350003_P01_FRONT-DECOR-BLOCK-ASSY-DR_CAD (Autodesk Fusion 360 design; units mm, degrees)
part number: 350003
description: FRONT - AIR SUPPLY ASSY - DR - RESERVED AIR SPACE | Cụm cấp gió khối phải | P01
part number: 350004
description: FRONT - DECOR SKIN - DR | Tấm ốp alu khối phải | P01
part number: 351301
description: FRONT - DECOR BACK PLATE - DR | Tấm hậu khối phải | P01
part number: 351302
description: FRONT - DECOR INNER FACE PANEL - DR - REMOVABLE | Tấm mặt trong tháo được khối phải | P01
part number: 351305
description: FRONT - DECOR INNER PANEL FELT - DR | Nỉ tấm trong khối phải | P01
part number: 351304
description: SEALS - ACCESS PANEL SEAL - 4.0 THICK - VERY SOFT FOAM PSA | Gioăng tấm thăm - xốp rất mềm dày 4.0, keo dán sẵn | P01
part number: 848013
description: FRONT - AIR INTAKE RISER - DR - RESERVED AIR SPACE | Ống gió đứng khối phải | P01
part number: 351402
description: FRONT - AIR TRANSITION - LOWER - DR - RESERVED AIR SPACE | Ống chuyển hướng dưới | P01
part number: 351403
description: FRONT - SUPPLY FAN BOX - DR - RESERVED AIR SPACE | Hộp quạt cấp | P01
part number: 351404
description: FRONT - AIR TRANSITION - UPPER - DR - RESERVED AIR SPACE | Ống chuyển hướng trên | P01
part number: 351405
description: FRONT - DECOR FRAME - DR | Khung trang trí phải (hàn) | P01
part number: 351306
description: FRONT - DECOR FRAME DR - FRONT RING BOTTOM | Mặt trước - khung khối phải - vòng trước - thanh dưới | P01
part number: 352301
description: FRONT - DECOR FRAME DR - FRONT RING FACET SIDE | Mặt trước - khung khối phải - vòng trước - thanh cạnh vát | P01
part number: 352302
description: FRONT - DECOR FRAME DR - FRONT RING TOP | Mặt trước - khung khối phải - vòng trước - thanh trên | P01
part number: 352303
description: FRONT - DECOR FRAME DR - FRONT RING DT JOINT | Mặt trước - khung khối phải - vòng trước - thanh nối khối trên | P01
part number: 352304
description: FRONT - DECOR FRAME DR - FRONT RING DIAGONAL | Mặt trước - khung khối phải - vòng trước - thanh chéo | P01
part number: 352305
description: FRONT - DECOR FRAME DR - FRONT RING GLASS EDGE | Mặt trước - khung khối phải - vòng trước - thanh mép kính | P01
part number: 352306
description: FRONT - DECOR FRAME DR - BACK RING BOTTOM | Mặt trước - khung khối phải - vòng sau - thanh dưới | P01
part number: 352307
description: FRONT - DECOR FRAME DR - BACK RING BOLT LINE | Mặt trước - khung khối phải - vòng sau - thanh hàng bu lông | P01
part number: 352308
description: FRONT - DECOR FRAME DR - BACK RING TOP | Mặt trước - khung khối phải - vòng sau - thanh trên | P01
part number: 352309
description: FRONT - DECOR FRAME DR - BACK RING DT JOINT | Mặt trước - khung khối phải - vòng sau - thanh nối khối trên | P01
part number: 352310
description: FRONT - DECOR FRAME DR - BACK RING DT LEDGE | Mặt trước - khung khối phải - vòng sau - thanh gờ đỡ khối trên | P01
part number: 352311
description: FRONT - DECOR FRAME DR - BACK RING DIAGONAL | Mặt trước - khung khối phải - vòng sau - thanh chéo | P01
part number: 352312
description: FRONT - DECOR FRAME DR - BACK RING GLASS EDGE | Mặt trước - khung khối phải - vòng sau - thanh mép kính | P01
part number: 352313
description: FRONT - DECOR FRAME DR - FRONT RING CROSS 724 | Mặt trước - khung khối phải - vòng trước - thanh ngang 724 | P01
part number: 352314
description: FRONT - DECOR FRAME DR - FRONT RING FAN BOX SHELF | Mặt trước - khung khối phải - vòng trước - thanh đỡ hộp quạt | P01
part number: 352315
description: FRONT - DECOR FRAME DR - FRONT RING CROSS OVER THE FAN BOX | Mặt trước - khung khối phải - vòng trước - thanh ngang trên hộp quạt | P01
part number: 352322
description: FRONT - DECOR FRAME DR - BACK RING BAND | Mặt trước - khung khối phải - vòng sau - thanh đai | P01
part number: 352316
description: FRONT - DECOR FRAME DR - FACET TUBE - 3 OFF | Mặt trước - khung khối phải - thanh mặt vát (3 thanh) | P01
part number: 352317
description: FRONT - DECOR FRAME DR - FACET TUBE FAN BOX SHELF | Mặt trước - khung khối phải - thanh mặt vát - đỡ hộp quạt | P01
part number: 352318
description: FRONT - DECOR FRAME DR - CHAMFER TUBE - 2 OFF | Mặt trước - khung khối phải - thanh vát (2 thanh) | P01
part number: 352319
description: FRONT - DECOR FRAME DR - DT JOINT TUBE SLANTED | Mặt trước - khung khối phải - thanh nối khối trên - xiên | P01
part number: 352320
Autodesk Fusion 360 part; units mm, degrees
(part 1 of 4)
sketch "FRONT - DR OUTLINE (BAND TOP TO ROOF, INNER EDGE ON THE GLASS LINES)" plane through (0, 0, 0) normal (0, 1, 0) x (1, 0, 0) in component "351301 FRONT - DECOR SKIN - DR"
  line L0 (946.8781, -110) -> (1250, -110)
  line L1 (1250, -110) -> (1250, -2400)
  line L2 (1250, -2400) -> (230, -2400)
  line L3 (230, -2400) -> (230, -2120)
  line L4 (230, -2120) -> (749, -1521)
  line L5 (749, -1521) -> (946.8781, -110)
  point P0 (-5000, 5000)
  dimension "d8636" = 5000
  dimension "d8637" = 5000
  dimension "d8638" = 5946.8781
  dimension "d8639" = 6250
  dimension "d8640" = 5230
  dimension "d8641" = 5749
  dimension "d8642" = 5110
  dimension "d8644" = 7120
  dimension "d8645" = 6521
  constraint vertical L1
  constraint vertical L3
  constraint horizontal L0
  constraint horizontal L2
  measures "d8636" horizontal distance of origin P0
  measures "d8637" vertical distance of origin P0
  measures "d8638" horizontal distance of L0.start P0
  measures "d8639" horizontal distance of L0.end P0
  measures "d8640" horizontal distance of L2.end P0
  measures "d8641" horizontal distance of L4.end P0
  measures "d8642" vertical distance of L0.start P0
  measures "d8644" vertical distance of L3.end P0
  measures "d8645" vertical distance of L4.end P0
extrude "EXTRUDE - DR OUTER SHAPE" add sketch "FRONT - DR OUTLINE (BAND TOP TO ROOF, INNER EDGE ON THE GLASS LINES)" along normal blind 205 from surface at -850 makes body 1 in component "351301 FRONT - DECOR SKIN - DR"
sketch "CORNER FACET - DR" plane through (0, 0, 0) normal (0, 0, 1) x (1, 0, 0) in component "351301 FRONT - DECOR SKIN - DR"
  line L0 (1052, -850) -> (1250, -672)
  line L1 (1250, -672) -> (1250, -850)
  line L2 (1250, -850) -> (1052, -850)
  point P0 (-5000, -5000)
  dimension "d8649" = 5000
  dimension "d8650" = 5000
  dimension "d8651" = 6052
  dimension "d8652" = 6250
  dimension "d8654" = 4150
  constraint vertical L1
  constraint horizontal L2
  measures "d8649" horizontal distance of origin P0
  measures "d8650" vertical distance of origin P0
  measures "d8651" horizontal distance of L0.start P0
  measures "d8652" horizontal distance of L0.end P0
  measures "d8654" vertical distance of L1.end P0
extrude "CUT - DR CORNER FACET" cut sketch "CORNER FACET - DR" along normal blind 2400 bodies 1 in component "351301 FRONT - DECOR SKIN - DR"
sketch "JOINT - DR TO DT (v1 LINE TO X 449)" plane through (0, 0, 0) normal (0, 0, 1) x (1, 0, 0) in component "351301 FRONT - DECOR SKIN - DR"
  line L0 (230, -850) -> (449, -672)
  line L1 (449, -672) -> (449, -645)
  line L2 (449, -645) -> (230, -645)
  line L3 (230, -645) -> (230, -850)
  point P0 (-5000, -5000)
  dimension "d8658" = 5000
  dimension "d8659" = 5000
  dimension "d8660" = 5449
  dimension "d8661" = 5230
  dimension "d8662" = 4150
  dimension "d8664" = 4355
  constraint vertical L1
  constraint vertical L3
  constraint horizontal L2
  measures "d8658" horizontal distance of origin P0
  measures "d8659" vertical distance of origin P0
  measures "d8660" horizontal distance of L0.end P0
  measures "d8661" horizontal distance of L2.end P0
  measures "d8662" vertical distance of L0.start P0
  measures "d8664" vertical distance of L1.end P0
extrude "CUT - DR TO DT JOINT" cut sketch "JOINT - DR TO DT (v1 LINE TO X 449)" along normal blind 280 from surface at 2120 bodies 1 in component "351301 FRONT - DECOR SKIN - DR"
sketch "CHAMFER - DR TOP FRONT" plane through (0, 0, 0) normal (1, 0, 0) x (0, 0, -1) in component "351301 FRONT - DECOR SKIN - DR"
  line L0 (-2200, -850) -> (-2400, -672)
  line L1 (-2400, -672) -> (-2400, -850)
  line L2 (-2400, -850) -> (-2200, -850)
  point P0 (5000, -5000)
  dimension "d8668" = 5000
  dimension "d8669" = 5000
  dimension "d8673" = 4150
  constraint vertical L1
  constraint horizontal L2
  measures "d8668" horizontal distance of origin P0
  measures "d8669" vertical distance of origin P0
  measures "d8673" vertical distance of L1.end P0
extrude "CUT - DR TOP CHAMFER" cut sketch "CHAMFER - DR TOP FRONT" along normal blind 2500 from surface at -1250 bodies 1 in component "351301 FRONT - DECOR SKIN - DR"
shell "SHELL - DR SKIN 3 MM (OPEN AT THE BACK AND AT DT)" thickness 3 removed faces 4 at (449, -663, 2213.3333) at (303, -722.3333, 2120) at (1083, -645, 1343.6667) at (376, -731.3333, 2240) on bodies 1 in component "351301 FRONT - DECOR SKIN - DR"
sketch "SLOT - GLASS CHANNEL ALONG THE INNER EDGE" plane through (0, 0, 0) normal (0, 1, 0) x (1, 0, 0) in component "351301 FRONT - DECOR SKIN - DR"
  line L0 (946.8781, -110) -> (962.0249, -110)
  line L1 (962.0249, -110) -> (763.2391, -1527.4726)
  line L2 (763.2391, -1527.4726) -> (249.8472, -2120)
  line L3 (249.8472, -2120) -> (230, -2120)
  line L4 (230, -2120) -> (749, -1521)
  line L5 (749, -1521) -> (946.8781, -110)
  point P0 (-5000, 5000)
  dimension "d8678" = 5000
  dimension "d8679" = 5000
  dimension "d8680" = 5946.8781
  dimension "d8682" = 5763.2391
  dimension "d8684" = 5230
  dimension "d8685" = 5749
  dimension "d8687" = 6527.4726
  dimension "d8689" = 6521
  constraint horizontal L0
  constraint horizontal L3
  measures "d8678" horizontal distance of origin P0
  measures "d8679" vertical distance of origin P0
  measures "d8680" horizontal distance of L0.start P0
  measures "d8682" horizontal distance of L1.end P0
  measures "d8684" horizontal distance of L3.end P0
  measures "d8685" horizontal distance of L4.end P0
  measures "d8687" vertical distance of L1.end P0
  measures "d8689" vertical distance of L4.end P0
extrude "CUT - SKIN SLOT FOR THE GLASS CHANNEL" cut sketch "SLOT - GLASS CHANNEL ALONG THE INNER EDGE" along normal blind 17 from surface at -707.5 bodies 1 in component "351301 FRONT - DECOR SKIN - DR"
sketch "INTAKE - DR BASE OPEN OVER THE MESH BAND PIECE" plane through (0, 0, 0) normal (0, 0, 1) x (1, 0, 0) in component "351301 FRONT - DECOR SKIN - DR"
  line L0 (949.4867, -847) -> (1050.8498, -847)
  line L1 (1050.8498, -847) -> (1247, -670.6629)
  line L2 (1247, -670.6629) -> (1247, -646.5)
  line L3 (1247, -646.5) -> (949.4867, -646.5)
  line L4 (949.4867, -646.5) -> (949.4867, -847)
  point P0 (-5000, -5000)
  dimension "d8693" = 5000
  dimension "d8694" = 5000
  dimension "d8695" = 6050.8498
  dimension "d8696" = 6247
  dimension "d8697" = 5949.4867
  dimension "d8698" = 4153
  dimension "d8699" = 4329.3371
  dimension "d8700" = 4353.5
  constraint vertical L2
  constraint vertical L4
  constraint horizontal L0
  constraint horizontal L3
  measures "d8693" horizontal distance of origin P0
  measures "d8694" vertical distance of origin P0
  measures "d8695" horizontal distance of L0.end P0
  measures "d8696" horizontal distance of L1.end P0
  measures "d8697" horizontal distance of L3.end P0
  measures "d8698" vertical distance of L0.start P0
  measures "d8699" vertical distance of L1.end P0
  measures "d8700" vertical distance of L2.end P0
extrude "CUT - BASE OPENING OVER THE BAND PIECE" cut sketch "INTAKE - DR BASE OPEN OVER THE MESH BAND PIECE" along normal blind 5 from surface at 109 bodies 1 in component "351301 FRONT - DECOR SKIN - DR"
sketch "OUTLINE - DR BACK PLATE (FIXED STRIP AND TOP BAND)" plane through (0, 0, 0) normal (0, 1, 0) x (1, 0, 0) in component "351302 FRONT - DECOR BACK PLATE - DR"
  line L0 (1203.5, -113) -> (1247, -113)
  line L1 (1247, -113) -> (1247, -2397)
  line L2 (1247, -2397) -> (449, -2397)
  line L3 (449, -2397) -> (449, -2155)
  line L4 (449, -2155) -> (1203.5, -2155)
  line L5 (1203.5, -2155) -> (1203.5, -113)
  point P0 (-5000, 5000)
  dimension "d8704" = 5000
  dimension "d8705" = 5000
  dimension "d8706" = 6247
  dimension "d8707" = 5449
  dimension "d8708" = 6203.5
  constraint vertical L1
  constraint vertical L3
  constraint vertical L5
  constraint horizontal L0
  constraint horizontal L2
  constraint horizontal L4
  measures "d8704" horizontal distance of origin P0
  measures "d8705" vertical distance of origin P0
  measures "d8706" horizontal distance of L0.end P0
  measures "d8707" horizontal distance of L2.end P0
  measures "d8708" horizontal distance of L4.end P0
extrude "EXTRUDE - DR BACK PLATE" add sketch "OUTLINE - DR BACK PLATE (FIXED STRIP AND TOP BAND)" along normal blind 1.5 from surface at -646.5 separate body makes body 2 in component "351302 FRONT - DECOR BACK PLATE - DR"
sketch "HOLES - J-FRONT-01 RIVNUTS (6)" plane through (0, 0, 0) normal (0, 1, 0) x (1, 0, 0) in component "351302 FRONT - DECOR BACK PLATE - DR"
  circle A0 centre (1224, -332.26) radius 5
  circle A1 centre (1224, -683.63) radius 5
  circle A2 centre (1224, -1035) radius 5
  circle A3 centre (1224, -1477.26) radius 5
  circle A4 centre (1224, -1828.63) radius 5
  circle A5 centre (1224, -2180) radius 5
  point P0 (-5000, 5000)
  dimension "d8715" = 5000
  dimension "d8716" = 5000
  dimension "d8718" = 5332.26
  dimension "d8719" = 10
  dimension "d8721" = 5683.63
  dimension "d8722" = 10
  dimension "d8724" = 6035
  dimension "d8725" = 10
  dimension "d8727" = 6477.26
  dimension "d8728" = 10
  dimension "d8730" = 6828.63
  dimension "d8731" = 10
  dimension "d8733" = 7180
  dimension "d8734" = 10
  measures "d8715" horizontal distance of origin P0
  measures "d8716" vertical distance of origin P0
  measures "d8718" vertical distance of P0 A0.centre
  measures "d8719" diameter of A0
  measures "d8721" vertical distance of P0 A1.centre
  measures "d8722" diameter of A1
  measures "d8724" vertical distance of P0 A2.centre
  measures "d8725" diameter of A2
  measures "d8727" vertical distance of P0 A3.centre
  measures "d8728" diameter of A3
  measures "d8730" vertical distance of P0 A4.centre
  measures "d8731" diameter of A4
  measures "d8733" vertical distance of P0 A5.centre
  measures "d8734" diameter of A5
extrude "CUT - J-FRONT-01 RIVNUT HOLES" cut sketch "HOLES - J-FRONT-01 RIVNUTS (6)" along normal blind 3.5 from surface at -647.5 bodies 2 in component "351302 FRONT - DECOR BACK PLATE - DR"
sketch "OUTLINE - DR INNER FACE PANEL (REMOVABLE, D-87, D-130)" plane through (0, 0, 0) normal (0, 1, 0) x (1, 0, 0) in component "351305 FRONT - DECOR INNER FACE PANEL - DR - REMOVABLE"
  line L0 (949.4867, -113) -> (1203.5, -113)
  line L1 (1203.5, -113) -> (1203.5, -2155)
  line L2 (1203.5, -2155) -> (449, -2155)
  line L3 (449, -2155) -> (449, -2120)
  line L4 (449, -2120) -> (233.9694, -2120)
  line L5 (233.9694, -2120) -> (751.8478, -1522.2945)
  line L6 (751.8478, -1522.2945) -> (949.4867, -113)
  point P0 (-5000, 5000)
  dimension "d8738" = 5000
  dimension "d8739" = 5000
  dimension "d8740" = 5949.4867
  dimension "d8741" = 6203.5
  dimension "d8742" = 5449
  dimension "d8744" = 5751.8478
  dimension "d8748" = 6522.2945
  constraint vertical L1
  constraint vertical L3
  constraint horizontal L0
  constraint horizontal L2
  constraint horizontal L4
  measures "d8738" horizontal distance of origin P0
  measures "d8739" vertical distance of origin P0
  measures "d8740" horizontal distance of L0.start P0
  measures "d8741" horizontal distance of L0.end P0
  measures "d8742" horizontal distance of L2.end P0
  measures "d8744" horizontal distance of L5.end P0
  measures "d8748" vertical distance of L5.end P0
extrude "EXTRUDE - DR INNER FACE PANEL" add sketch "OUTLINE - DR INNER FACE PANEL (REMOVABLE, D-87, D-130)" along normal blind 3 from surface at -644.14 separate body makes body 3 in component "351305 FRONT - DECOR INNER FACE PANEL - DR - REMOVABLE"
sketch "OPENING - INTO THE AIR COLUMN TOP" plane through (0, 0, 0) normal (0, 1, 0) x (1, 0, 0) in component "351305 FRONT - DECOR INNER FACE PANEL - DR - REMOVABLE"
  line L0 (961, -1895) -> (1146, -1895)
  line L1 (1146, -1895) -> (1146, -2102)
  line L2 (1146, -2102) -> (961, -2102)
  line L3 (961, -2102) -> (961, -1895)
  point P0 (-5000, 5000)
  dimension "d8752" = 5000
  dimension "d8753" = 5000
  dimension "d8754" = 6146
  dimension "d8755" = 5961
  dimension "d8756" = 6895
  dimension "d8757" = 7102
  constraint vertical L1
  constraint vertical L3
  constraint horizontal L0
  constraint horizontal L2
  measures "d8752" horizontal distance of origin P0
  measures "d8753" vertical distance of origin P0
  measures "d8754" horizontal distance of L0.end P0
  measures "d8755" horizontal distance of L2.end P0
  measures "d8756" vertical distance of L0.start P0
  measures "d8757" vertical distance of L1.end P0
extrude "CUT - OPENING INTO THE AIR COLUMN" cut sketch "OPENING - INTO THE AIR COLUMN TOP" along normal blind 5 from surface at -645.14 bodies 3 in component "351305 FRONT - DECOR INNER FACE PANEL - DR - REMOVABLE"
sketch "HOLES - THE PANEL'S SCREWS (21)" plane through (0, 0, 0) normal (0, 1, 0) x (1, 0, 0) in component "351305 FRONT - DECOR INNER FACE PANEL - DR - REMOVABLE"
  circle A0 centre (1000.2299, -130) radius 3.5
  circle A1 centre (1146, -130) radius 3.5
  circle A2 centre (1186, -170) radius 3.5
  circle A3 centre (1186, -556.2) radius 3.5
  circle A4 centre (1186, -942.4) radius 3.5
  circle A5 centre (1186, -1328.6) radius 3.5
  circle A6 centre (1186, -1714.8) radius 3.5
  circle A7 centre (1186, -2101) radius 3.5
  circle A8 centre (1143.5, -2141) radius 3.5
  circle A9 centre (821.25, -2141) radius 3.5
  circle A10 centre (499, -2141) radius 3.5
  circle A11 centre (419, -2110) radius 3.5
  circle A12 centre (299.8348, -2110) radius 3.5
  circle A13 centre (286.0282, -2079.7691) radius 3.5
  circle A14 centre (512.0116, -1818.9521) radius 3.5
  circle A15 centre (737.995, -1558.135) radius 3.5
  circle A16 centre (769.7436, -1488.2918) radius 3.5
  circle A17 centre (812.0577, -1186.5645) radius 3.5
  circle A18 centre (854.3718, -884.8373) radius 3.5
  circle A19 centre (896.6859, -583.11) radius 3.5
  circle A20 centre (939, -281.3828) radius 3.5
  point P0 (-5000, 5000)
  dimension "d8761" = 5000
  dimension "d8762" = 5000
  dimension "d8763" = 6000.2299
  dimension "d8764" = 5130
  dimension "d8765" = 7
  dimension "d8766" = 6146
  dimension "d8767" = 5130
  dimension "d8768" = 7
  dimension "d8769" = 6186
  dimension "d8770" = 5170
  dimension "d8771" = 7
  dimension "d8772" = 6186
  dimension "d8773" = 5556.2
  dimension "d8774" = 7
  dimension "d8775" = 6186
  dimension "d8776" = 5942.4
  dimension "d8777" = 7
  dimension "d8778" = 6186
  dimension "d8779" = 6328.6
  dimension "d8780" = 7
  dimension "d8781" = 6186
  dimension "d8782" = 6714.8
  dimension "d8783" = 7
  dimension "d8784" = 6186
  dimension "d8785" = 7101
  dimension "d8786" = 7
  dimension "d8787" = 6143.5
  dimension "d8788" = 7141
  dimension "d8789" = 7
  dimension "d8790" = 5821.25
  dimension "d8791" = 7141
  dimension "d8792" = 7
  dimension "d8793" = 5499
  dimension "d8794" = 7141
  dimension "d8795" = 7
  dimension "d8796" = 5419
  dimension "d8797" = 7110
  dimension "d8798" = 7
  dimension "d8799" = 5299.8348
  dimension "d8800" = 7110
  dimension "d8801" = 7
  dimension "d8802" = 5286.0282
  dimension "d8803" = 7079.7691
  dimension "d8804" = 7
  dimension "d8805" = 5512.0116
  dimension "d8806" = 6818.9521
  dimension "d8807" = 7
  dimension "d8808" = 5737.995
  dimension "d8809" = 6558.135
  dimension "d8810" = 7
  dimension "d8811" = 5769.7436
  dimension "d8812" = 6488.2918
  dimension "d8813" = 7
  dimension "d8814" = 5812.0577
  dimension "d8815" = 6186.5645
  dimension "d8816" = 7
  dimension "d8817" = 5854.3718
  dimension "d8818" = 5884.8373
  dimension "d8819" = 7
  dimension "d8820" = 5896.6859
  dimension "d8821" = 5583.11
  dimension "d8822" = 7
  dimension "d8823" = 5939
  dimension "d8824" = 5281.3828
  dimension "d8825" = 7
  measures "d8761" horizontal distance of origin P0
  measures "d8762" vertical distance of origin P0
  measures "d8763" horizontal distance of P0 A0.centre
  measures "d8764" vertical distance of P0 A0.centre
  measures "d8765" diameter of A0
  measures "d8766" horizontal distance of P0 A1.centre
  measures "d8767" vertical distance of P0 A1.centre
  measures "d8768" diameter of A1
  measures "d8769" horizontal distance of P0 A2.centre
  measures "d8770" vertical distance of P0 A2.centre
  measures "d8771" diameter of A2
  measures "d8772" horizontal distance of P0 A3.centre
  measures "d8773" vertical distance of P0 A3.centre
  measures "d8774" diameter of A3
  measures "d8775" horizontal distance of P0 A4.centre
  measures "d8776" vertical distance of P0 A4.centre
  measures "d8777" diameter of A4
  measures "d8778" horizontal distance of P0 A5.centre
  measures "d8779" vertical distance of P0 A5.centre
  measures "d8780" diameter of A5
  measures "d8781" horizontal distance of P0 A6.centre
  measures "d8782" vertical distance of P0 A6.centre
  measures "d8783" diameter of A6
  measures "d8784" horizontal distance of P0 A7.centre
  measures "d8785" vertical distance of P0 A7.centre
  measures "d8786" diameter of A7
  measures "d8787" horizontal distance of P0 A8.centre
  measures "d8788" vertical distance of P0 A8.centre
  measures "d8789" diameter of A8
  measures "d8790" horizontal distance of P0 A9.centre
  measures "d8791" vertical distance of P0 A9.centre
  measures "d8792" diameter of A9
  measures "d8793" horizontal distance of P0 A10.centre
  measures "d8794" vertical distance of P0 A10.centre
  measures "d8795" diameter of A10
  measures "d8796" horizontal distance of P0 A11.centre
  measures "d8797" vertical distance of P0 A11.centre
  measures "d8798" diameter of A11
  measures "d8799" horizontal distance of P0 A12.centre
  measures "d8800" vertical distance of P0 A12.centre
  measures "d8801" diameter of A12
  measures "d8802" horizontal distance of P0 A13.centre
  measures "d8803" vertical distance of P0 A13.centre
  measures "d8804" diameter of A13
  measures "d8805" horizontal distance of P0 A14.centre
  measures "d8806" vertical distance of P0 A14.centre
  measures "d8807" diameter of A14
  measures "d8808" horizontal distance of P0 A15.centre
  measures "d8809" vertical distance of P0 A15.centre
  measures "d8810" diameter of A15
  measures "d8811" horizontal distance of P0 A16.centre
  measures "d8812" vertical distance of P0 A16.centre
  measures "d8813" diameter of A16
  measures "d8814" horizontal distance of P0 A17.centre
  measures "d8815" vertical distance of P0 A17.centre
  measures "d8816" diameter of A17
  measures "d8817" horizontal distance of P0 A18.centre
  measures "d8818" vertical distance of P0 A18.centre
  measures "d8819" diameter of A18
  measures "d8820" horizontal distance of P0 A19.centre
  measures "d8821" vertical distance of P0 A19.centre
  measures "d8822" diameter of A19
  measures "d8823" horizontal distance of P0 A20.centre
  measures "d8824" vertical distance of P0 A20.centre
  measures "d8825" diameter of A20
extrude "CUT - THE PANEL'S SCREW HOLES" cut sketch "HOLES - THE PANEL'S SCREWS (21)" along normal blind 5 from surface at -645.14 bodies 3 in component "351305 FRONT - DECOR INNER FACE PANEL - DR - REMOVABLE"
sketch "HOLES - AIR COLUMN HOOK STUD RIVNUTS (2)" plane through (0, 0, 0) normal (0, 1, 0) x (1, 0, 0) in component "351305 FRONT - DECOR INNER FACE PANEL - DR - REMOVABLE"
  circle A0 centre (971, -1700) radius 5
  circle A1 centre (971, -1850) radius 5
  point P0 (-5000, 5000)
  dimension "d8829" = 5000
  dimension "d8830" = 5000
  dimension "d8832" = 6700
  dimension "d8833" = 10
  dimension "d8835" = 6850
  dimension "d8836" = 10
  measures "d8829" horizontal distance of origin P0
  measures "d8830" vertical distance of origin P0
  measures "d8832" vertical distance of P0 A0.centre
  measures "d8833" diameter of A0
  measures "d8835" vertical distance of P0 A1.centre
  measures "d8836" diameter of A1
extrude "CUT - HOOK STUD RIVNUT HOLES" cut sketch "HOLES - AIR COLUMN HOOK STUD RIVNUTS (2)" along normal blind 5 from surface at -645.14 bodies 3 in component "351305 FRONT - DECOR INNER FACE PANEL - DR - REMOVABLE"
sketch "OUTLINE - DR INNER FACE PANEL FELT" plane through (0, 0, 0) normal (0, 1, 0) x (1, 0, 0) in component "351304 FRONT - DECOR INNER PANEL FELT - DR"
  line L0 (949, -116.4706) -> (949, -2120)
  line L1 (949, -2120) -> (233.9694, -2120)
  line L2 (233.9694, -2120) -> (751.8478, -1522.2945)
  line L3 (751.8478, -1522.2945) -> (949, -116.4706)
  point P0 (-5000, 5000)
  dimension "d8840" = 5000
  dimension "d8841" = 5000
  dimension "d8842" = 5949
  dimension "d8844" = 5751.8478
  dimension "d8845" = 5116.4706
  dimension "d8847" = 6522.2945
  constraint vertical L0
  constraint horizontal L1
  measures "d8840" horizontal distance of origin P0
  measures "d8841" vertical distance of origin P0
  measures "d8842" horizontal distance of L0.start P0
  measures "d8844" horizontal distance of L2.end P0
  measures "d8845" vertical distance of L0.start P0
  measures "d8847" vertical distance of L2.end P0
extrude "EXTRUDE - FELT 9" add sketch "OUTLINE - DR INNER FACE PANEL FELT" along normal blind 9 from surface at -641.14 separate body makes body 4 in component "351304 FRONT - DECOR INNER PANEL FELT - DR"
sketch "HOLES - OVER THE PANEL'S SCREW HEADS, PLUGGED (10)" plane through (0, 0, 0) normal (0, 1, 0) x (1, 0, 0) in component "351304 FRONT - DECOR INNER PANEL FELT - DR"
  circle A0 centre (419, -2110) radius 7
  circle A1 centre (299.8348, -2110) radius 7
  circle A2 centre (286.0282, -2079.7691) radius 7
  circle A3 centre (512.0116, -1818.9521) radius 7
  circle A4 centre (737.995, -1558.135) radius 7
  circle A5 centre (769.7436, -1488.2918) radius 7
  circle A6 centre (812.0577, -1186.5645) radius 7
  circle A7 centre (854.3718, -884.8373) radius 7
  circle A8 centre (896.6859, -583.11) radius 7
  circle A9 centre (939, -281.3828) radius 7
  point P0 (-5000, 5000)
  dimension "d8851" = 5000
  dimension "d8852" = 5000
  dimension "d8853" = 5419
  dimension "d8854" = 7110
  dimension "d8855" = 14
  dimension "d8856" = 5299.8348
  dimension "d8857" = 7110
  dimension "d8858" = 14
  dimension "d8859" = 5286.0282
  dimension "d8860" = 7079.7691
  dimension "d8861" = 14
  dimension "d8862" = 5512.0116
  dimension "d8863" = 6818.9521
  dimension "d8864" = 14
  dimension "d8865" = 5737.995
  dimension "d8866" = 6558.135
  dimension "d8867" = 14
  dimension "d8868" = 5769.7436
  dimension "d8869" = 6488.2918
  dimension "d8870" = 14
  dimension "d8871" = 5812.0577
  dimension "d8872" = 6186.5645
  dimension "d8873" = 14
  dimension "d8874" = 5854.3718
  dimension "d8875" = 5884.8373
  dimension "d8876" = 14
  dimension "d8877" = 5896.6859
  dimension "d8878" = 5583.11
  dimension "d8879" = 14
  dimension "d8880" = 5939
  dimension "d8881" = 5281.3828
  dimension "d8882" = 14
  measures "d8851" horizontal distance of origin P0
  measures "d8852" vertical distance of origin P0
  measures "d8853" horizontal distance of P0 A0.centre
  measures "d8854" vertical distance of P0 A0.centre
  measures "d8855" diameter of A0
  measures "d8856" horizontal distance of P0 A1.centre
  measures "d8857" vertical distance of P0 A1.centre
  measures "d8858" diameter of A1
  measures "d8859" horizontal distance of P0 A2.centre
  measures "d8860" vertical distance of P0 A2.centre
  measures "d8861" diameter of A2
  measures "d8862" horizontal distance of P0 A3.centre
  measures "d8863" vertical distance of P0 A3.centre
  measures "d8864" diameter of A3
  measures "d8865" horizontal distance of P0 A4.centre
  measures "d8866" vertical distance of P0 A4.centre
  measures "d8867" diameter of A4
  measures "d8868" horizontal distance of P0 A5.centre
  measures "d8869" vertical distance of P0 A5.centre
  measures "d8870" diameter of A5
  measures "d8871" horizontal distance of P0 A6.centre
  measures "d8872" vertical distance of P0 A6.centre
  measures "d8873" diameter of A6
  measures "d8874" horizontal distance of P0 A7.centre
  measures "d8875" vertical distance of P0 A7.centre
  measures "d8876" diameter of A7
  measures "d8877" horizontal distance of P0 A8.centre
  measures "d8878" vertical distance of P0 A8.centre
  measures "d8879" diameter of A8
  measures "d8880" horizontal distance of P0 A9.centre
  measures "d8881" vertical distance of P0 A9.centre
  measures "d8882" diameter of A9
extrude "CUT - FELT HOLES OVER THE SCREW HEADS" cut sketch "HOLES - OVER THE PANEL'S SCREW HEADS, PLUGGED (10)" along normal blind 11 from surface at -642.14 bodies 4 in component "351304 FRONT - DECOR INNER PANEL FELT - DR"
sketch "OUTLINE - 848013 SEAL, OUTER EDGE" plane through (0, 0, 0) normal (0, 1, 0) x (1, 0, 0) in component "848013 SEALS - ACCESS PANEL SEAL - 4.0 THICK - VERY SOFT FOAM PSA"
  line L0 (956.7517, -126) -> (1190, -126)
  line L1 (1190, -126) -> (1190, -2145)
  line L2 (1190, -2145) -> (455, -2145)
  line L3 (455, -2145) -> (455, -2114)
  line L4 (455, -2114) -> (251.0765, -2114)
  line L5 (251.0765, -2114) -> (760.3913, -1526.1781)
  line L6 (760.3913, -1526.1781) -> (956.7517, -126)
  point P0 (-5000, 5000)
  dimension "d8886" = 5000
  dimension "d8887" = 5000
  dimension "d8888" = 5956.7517
  dimension "d8889" = 6190
  dimension "d8890" = 5455
  dimension "d8891" = 5251.0765
  dimension "d8892" = 5760.3913
  dimension "d8893" = 5126
  dimension "d8894" = 7145
  dimension "d8895" = 7114
  dimension "d8896" = 6526.1781
  constraint vertical L1
  constraint vertical L3
  constraint horizontal L0
  constraint horizontal L2
  constraint horizontal L4
  measures "d8886" horizontal distance of origin P0
  measures "d8887" vertical distance of origin P0
  measures "d8888" horizontal distance of L0.start P0
  measures "d8889" horizontal distance of L0.end P0
  measures "d8890" horizontal distance of L2.end P0
  measures "d8891" horizontal distance of L4.end P0
  measures "d8892" horizontal distance of L5.end P0
  measures "d8893" vertical distance of L0.start P0
  measures "d8894" vertical distance of L1.end P0
  measures "d8895" vertical distance of L3.end P0
  measures "d8896" vertical distance of L5.end P0
extrude "EXTRUDE - 848013 SEAL (SQUEEZED TO THE STOP GAP)" add sketch "OUTLINE - 848013 SEAL, OUTER EDGE" along normal blind 2.36 from surface at -646.5 separate body makes body 5 in component "848013 SEALS - ACCESS PANEL SEAL - 4.0 THICK - VERY SOFT FOAM PSA"
sketch "OUTLINE - 848013 SEAL, INNER EDGE" plane through (0, 0, 0) normal (0, 1, 0) x (1, 0, 0) in component "848013 SEALS - ACCESS PANEL SEAL - 4.0 THICK - VERY SOFT FOAM PSA"
  line L0 (963.708, -134) -> (1182, -134)
  line L1 (1182, -134) -> (1182, -2137)
  line L2 (1182, -2137) -> (463, -2137)
  line L3 (463, -2137) -> (463, -2106)
  line L4 (463, -2106) -> (268.5932, -2106)
  line L5 (268.5932, -2106) -> (767.9854, -1529.6302)
  line L6 (767.9854, -1529.6302) -> (963.708, -134)
  point P0 (-5000, 5000)
  dimension "d8900" = 5000
  dimension "d8901" = 5000
  dimension "d8902" = 5963.708
  dimension "d8903" = 6182
  dimension "d8904" = 5463
  dimension "d8905" = 5268.5932
  dimension "d8906" = 5767.9854
  dimension "d8907" = 5134
  dimension "d8908" = 7137
  dimension "d8909" = 7106
  dimension "d8910" = 6529.6302
  constraint vertical L1
  constraint vertical L3
  constraint horizontal L0
  constraint horizontal L2
  constraint horizontal L4
  measures "d8900" horizontal distance of origin P0
  measures "d8901" vertical distance of origin P0
  measures "d8902" horizontal distance of L0.start P0
  measures "d8903" horizontal distance of L0.end P0
  measures "d8904" horizontal distance of L2.end P0
  measures "d8905" horizontal distance of L4.end P0
  measures "d8906" horizontal distance of L5.end P0
  measures "d8907" vertical distance of L0.start P0
  measures "d8908" vertical distance of L1.end P0
  measures "d8909" vertical distance of L3.end P0
  measures "d8910" vertical distance of L5.end P0
extrude "CUT - 848013 SEAL, INSIDE THE LOOP" cut sketch "OUTLINE - 848013 SEAL, INNER EDGE" along normal blind 4.36 from surface at -647.5 bodies 5 in component "848013 SEALS - ACCESS PANEL SEAL - 4.0 THICK - VERY SOFT FOAM PSA"
sketch "PLAN - INTAKE RISER OUTER" plane through (0, 0, 0) normal (0, 0, 1) x (1, 0, 0) in component "351402 FRONT - AIR INTAKE RISER - DR - RESERVED AIR SPACE"
  line L0 (959, -803) -> (1098, -803)
  line L1 (1098, -803) -> (1098, -648)
  line L2 (1098, -648) -> (959, -648)
  line L3 (959, -648) -> (959, -803)
  point P0 (-5000, -5000)
  dimension "d8914" = 5000
  dimension "d8915" = 5000
  dimension "d8916" = 6098
  dimension "d8917" = 5959
  dimension "d8918" = 4197
  dimension "d8919" = 4352
  constraint vertical L1
  constraint vertical L3
  constraint horizontal L0
  constraint horizontal L2
  measures "d8914" horizontal distance of origin P0
  measures "d8915" vertical distance of origin P0
  measures "d8916" horizontal distance of L0.end P0
  measures "d8917" horizontal distance of L2.end P0
  measures "d8918" vertical distance of L0.start P0
  measures "d8919" vertical distance of L1.end P0
extrude "EXTRUDE - INTAKE RISER" add sketch "PLAN - INTAKE RISER OUTER" along normal blind 1192 from surface at 253 separate body makes body 6 in component "351402 FRONT - AIR INTAKE RISER - DR - RESERVED AIR SPACE"
sketch "PLAN - INTAKE RISER BORE" plane through (0, 0, 0) normal (0, 0, 1) x (1, 0, 0) in component "351402 FRONT - AIR INTAKE RISER - DR - RESERVED AIR SPACE"
  line L0 (960, -802) -> (1097, -802)
  line L1 (1097, -802) -> (1097, -649)
  line L2 (1097, -649) -> (960, -649)
  line L3 (960, -649) -> (960, -802)
  point P0 (-5000, -5000)
  dimension "d8923" = 5000
  dimension "d8924" = 5000
  dimension "d8925" = 6097
  dimension "d8926" = 5960
  dimension "d8927" = 4198
  dimension "d8928" = 4351
  constraint vertical L1
  constraint vertical L3
  constraint horizontal L0
  constraint horizontal L2
  measures "d8923" horizontal distance of origin P0
  measures "d8924" vertical distance of origin P0
  measures "d8925" horizontal distance of L0.end P0
  measures "d8926" horizontal distance of L2.end P0
  measures "d8927" vertical distance of L0.start P0
  measures "d8928" vertical distance of L1.end P0
extrude "CUT - INTAKE RISER BORE" cut sketch "PLAN - INTAKE RISER BORE" along normal blind 1194 from surface at 252 bodies 6 in component "351402 FRONT - AIR INTAKE RISER - DR - RESERVED AIR SPACE"
sketch "SIDE - LOWER TRANSITION SPACE" plane through (0, 0, 0) normal (0, 1, 0) x (1, 0, 0) in component "351403 FRONT - AIR TRANSITION - LOWER - DR - RESERVED AIR SPACE"
  line L0 (959, -1445) -> (1098, -1445)
  line L1 (1098, -1445) -> (980, -1650)
  line L2 (980, -1650) -> (680, -1650)
  line L3 (680, -1650) -> (959, -1445)
  point P0 (-5000, 5000)
  dimension "d8932" = 5000
  dimension "d8933" = 5000
  dimension "d8934" = 5959
  dimension "d8935" = 6098
  dimension "d8936" = 5980
  dimension "d8937" = 5680
  dimension "d8939" = 6650
  constraint horizontal L0
  constraint horizontal L2
  measures "d8932" horizontal distance of origin P0
  measures "d8933" vertical distance of origin P0
  measures "d8934" horizontal distance of L0.start P0
  measures "d8935" horizontal distance of L0.end P0
  measures "d8936" horizontal distance of L1.end P0
  measures "d8937" horizontal distance of L2.end P0
  measures "d8939" vertical distance of L1.end P0
extrude "EXTRUDE - LOWER TRANSITION SPACE" add sketch "SIDE - LOWER TRANSITION SPACE" along normal blind 155 from surface at -803 separate body makes body 7 in component "351403 FRONT - AIR TRANSITION - LOWER - DR - RESERVED AIR SPACE"
sketch "PLAN - FAN BOX OUTER" plane through (0, 0, 0) normal (0, 0, 1) x (1, 0, 0) in component "351404 FRONT - SUPPLY FAN BOX - DR - RESERVED AIR SPACE"
  line L0 (680, -819) -> (980, -819)
  line L1 (980, -819) -> (980, -664)
  line L2 (980, -664) -> (680, -664)
  line L3 (680, -664) -> (680, -819)
  point P0 (-5000, -5000)
  dimension "d8943" = 5000
  dimension "d8944" = 5000
  dimension "d8945" = 5980
  dimension "d8946" = 5680
  dimension "d8947" = 4181
  dimension "d8948" = 4336
  constraint vertical L1
  constraint vertical L3
  constraint horizontal L0
  constraint horizontal L2
  measures "d8943" horizontal distance of origin P0
  measures "d8944" vertical distance of origin P0
  measures "d8945" horizontal distance of L0.end P0
  measures "d8946" horizontal distance of L2.end P0
  measures "d8947" vertical distance of L0.start P0
  measures "d8948" vertical distance of L1.end P0
extrude "EXTRUDE - FAN BOX" add sketch "PLAN - FAN BOX OUTER" along normal blind 300 from surface at 1650 separate body makes body 8 in component "351404 FRONT - SUPPLY FAN BOX - DR - RESERVED AIR SPACE"
sketch "PLAN - FAN BOX BORE" plane through (0, 0, 0) normal (0, 0, 1) x (1, 0, 0) in component "351404 FRONT - SUPPLY FAN BOX - DR - RESERVED AIR SPACE"
  line L0 (682, -817) -> (978, -817)
  line L1 (978, -817) -> (978, -666)
  line L2 (978, -666) -> (682, -666)
  line L3 (682, -666) -> (682, -817)
  point P0 (-5000, -5000)
  dimension "d8952" = 5000
  dimension "d8953" = 5000
  dimension "d8954" = 5978
  dimension "d8955" = 5682
  dimension "d8956" = 4183
  dimension "d8957" = 4334
  constraint vertical L1
  constraint vertical L3
  constraint horizontal L0
  constraint horizontal L2
  measures "d8952" horizontal distance of origin P0
  measures "d8953" vertical distance of origin P0
  measures "d8954" horizontal distance of L0.end P0
  measures "d8955" horizontal distance of L2.end P0
  measures "d8956" vertical distance of L0.start P0
  measures "d8957" vertical distance of L1.end P0
extrude "CUT - FAN BOX BORE" cut sketch "PLAN - FAN BOX BORE" along normal blind 302 from surface at 1649 bodies 8 in component "351404 FRONT - SUPPLY FAN BOX - DR - RESERVED AIR SPACE"
sketch "PLAN - UPPER TRANSITION SPACE" plane through (0, 0, 0) normal (0, 0, 1) x (1, 0, 0) in component "351405 FRONT - AIR TRANSITION - UPPER - DR - RESERVED AIR SPACE"
  line L0 (680, -819) -> (980, -819)
  line L1 (980, -819) -> (980, -668)
  line L2 (980, -668) -> (1146, -668)
  line L3 (1146, -668) -> (1146, -646.5)
  line L4 (1146, -646.5) -> (680, -646.5)
  line L5 (680, -646.5) -> (680, -819)
  point P0 (-5000, -5000)
  dimension "d8961" = 5000
  dimension "d8962" = 5000
  dimension "d8963" = 5980
  dimension "d8964" = 6146
  dimension "d8965" = 5680
  dimension "d8966" = 4181
  dimension "d8967" = 4332
  dimension "d8968" = 4353.5
  constraint vertical L1
  constraint vertical L3
  constraint vertical L5
  constraint horizontal L0
  constraint horizontal L2
  constraint horizontal L4
  measures "d8961" horizontal distance of origin P0
  measures "d8962" vertical distance of origin P0
  measures "d8963" horizontal distance of L0.end P0
  measures "d8964" horizontal distance of L2.end P0
  measures "d8965" horizontal distance of L4.end P0
  measures "d8966" vertical distance of L0.start P0
  measures "d8967" vertical distance of L1.end P0
  measures "d8968" vertical distance of L3.end P0
extrude "EXTRUDE - UPPER TRANSITION SPACE" add sketch "PLAN - UPPER TRANSITION SPACE" along normal blind 152 from surface at 1950 separate body makes body 9 in component "351405 FRONT - AIR TRANSITION - UPPER - DR - RESERVED AIR SPACE"
sketch "PLAN - UPPER TRANSITION DROP TO THE OPENING" plane through (0, 0, 0) normal (0, 0, 1) x (1, 0, 0) in component "351405 FRONT - AIR TRANSITION - UPPER - DR - RESERVED AIR SPACE"
  line L0 (980, -668) -> (1146, -668)
  line L1 (1146, -668) -> (1146, -646.5)
  line L2 (1146, -646.5) -> (980, -646.5)
  line L3 (980, -646.5) -> (980, -668)
  point P0 (-5000, -5000)
  dimension "d8972" = 5000
  dimension "d8973" = 5000
  dimension "d8974" = 6146
  dimension "d8975" = 5980
  dimension "d8976" = 4332
  dimension "d8977" = 4353.5
  constraint vertical L1
  constraint vertical L3
  constraint horizontal L0
  constraint horizontal L2
  measures "d8972" horizontal distance of origin P0
  measures "d8973" vertical distance of origin P0
  measures "d8974" horizontal distance of L0.end P0
  measures "d8975" horizontal distance of L2.end P0
  measures "d8976" vertical distance of L0.start P0
  measures "d8977" vertical distance of L1.end P0
extrude "EXTRUDE - UPPER TRANSITION DROP" add sketch "PLAN - UPPER TRANSITION DROP TO THE OPENING" along normal blind 55 from surface at 1895 separate body makes body 10 in component "351405 FRONT - AIR TRANSITION - UPPER - DR - RESERVED AIR SPACE"
sketch "TUBE F01 - FRONT RING BOTTOM" plane through (0, 0, 0) normal (0, 1, 0) x (1, 0, 0) in component "352301 FRONT - DECOR FRAME DR - FRONT RING BOTTOM"
  line L0 (952.9368, -110) -> (1049.6995, -110)
  line L1 (1049.6995, -110) -> (1029.6995, -130)
  line L2 (1029.6995, -130) -> (970.3277, -130)
  line L3 (970.3277, -130) -> (952.9368, -110)
  point P0 (-5000, 5000)
  dimension "d8981" = 5000
  dimension "d8982" = 5000
  dimension "d8984" = 6049.6995
  dimension "d8985" = 6029.6995
  dimension "d8986" = 5970.3277
  dimension "d8988" = 5130
  constraint horizontal L0
  constraint horizontal L2
  measures "d8981" horizontal distance of origin P0
  measures "d8982" vertical distance of origin P0
  measures "d8984" horizontal distance of L0.end P0
  measures "d8985" horizontal distance of L1.end P0
  measures "d8986" horizontal distance of L2.end P0
  measures "d8988" vertical distance of L1.end P0
extrude "EXTRUDE - TUBE F01" add sketch "TUBE F01 - FRONT RING BOTTOM" along normal blind 20 from surface at -844 separate body makes body 11 in component "352301 FRONT - DECOR FRAME DR - FRONT RING BOTTOM"
shell "SHELL - TUBE F01 (ENDS OPEN)" thickness 1 removed faces 2 at (964.5307, -830.6667, 123.3333) at (1043.0328, -830.6667, 116.6667) on bodies 11 in component "352301 FRONT - DECOR FRAME DR - FRONT RING BOTTOM"
sketch "TUBE F02 - FRONT RING FACET SIDE" plane through (0, 0, 0) normal (0, 1, 0) x (1, 0, 0) in component "352302 FRONT - DECOR FRAME DR - FRONT RING FACET SIDE"
  line L0 (1049.6995, -110) -> (1049.6995, -2197.7167)
  line L1 (1049.6995, -2197.7167) -> (1029.6995, -2177.7167)
  line L2 (1029.6995, -2177.7167) -> (1029.6995, -130)
  line L3 (1029.6995, -130) -> (1049.6995, -110)
  point P0 (-5000, 5000)
  dimension "d8993" = 5000
  dimension "d8994" = 5000
  dimension "d8995" = 6049.6995
  dimension "d8996" = 6029.6995
  dimension "d8998" = 7197.7167
  dimension "d8999" = 7177.7167
  dimension "d9000" = 5130
  constraint vertical L0
  constraint vertical L2
  measures "d8993" horizontal distance of origin P0
  measures "d8994" vertical distance of origin P0
  measures "d8995" horizontal distance of L0.start P0
  measures "d8996" horizontal distance of L1.end P0
  measures "d8998" vertical distance of L0.end P0
  measures "d8999" vertical distance of L1.end P0
  measures "d9000" vertical distance of L2.end P0
extrude "EXTRUDE - TUBE F02" add sketch "TUBE F02 - FRONT RING FACET SIDE" along normal blind 20 from surface at -844 separate body makes body 12 in component "352302 FRONT - DECOR FRAME DR - FRONT RING FACET SIDE"
shell "SHELL - TUBE F02 (ENDS OPEN)" thickness 1 removed faces 2 at (1036.3662, -837.3333, 123.3333) at (1043.0328, -830.6667, 2191.05) on bodies 12 in component "352302 FRONT - DECOR FRAME DR - FRONT RING FACET SIDE"
sketch "TUBE F03 - FRONT RING TOP" plane through (0, 0, 0) normal (0, 1, 0) x (1, 0, 0) in component "352303 FRONT - DECOR FRAME DR - FRONT RING TOP"
  line L0 (1049.6995, -2197.7167) -> (261.9888, -2197.7167)
  line L1 (261.9888, -2197.7167) -> (281.9888, -2177.7167)
  line L2 (281.9888, -2177.7167) -> (1029.6995, -2177.7167)
  line L3 (1029.6995, -2177.7167) -> (1049.6995, -2197.7167)
  point P0 (-5000, 5000)
  dimension "d9005" = 5000
  dimension "d9006" = 5000
  dimension "d9007" = 6049.6995
  dimension "d9008" = 5261.9888
  dimension "d9009" = 5281.9888
  dimension "d9010" = 6029.6995
  dimension "d9011" = 7197.7167
  dimension "d9012" = 7177.7167
  constraint horizontal L0
  constraint horizontal L2
  measures "d9005" horizontal distance of origin P0
  measures "d9006" vertical distance of origin P0
  measures "d9007" horizontal distance of L0.start P0
  measures "d9008" horizontal distance of L0.end P0
  measures "d9009" horizontal distance of L1.end P0
  measures "d9010" horizontal distance of L2.end P0
  measures "d9011" vertical distance of L0.start P0
  measures "d9012" vertical distance of L1.end P0
extrude "EXTRUDE - TUBE F03" add sketch "TUBE F03 - FRONT RING TOP" along normal blind 20 from surface at -844 separate body makes body 13 in component "352303 FRONT - DECOR FRAME DR - FRONT RING TOP"
shell "SHELL - TUBE F03 (ENDS OPEN)" thickness 1 removed faces 2 at (1036.3662, -830.6667, 2184.3833) at (268.6554, -837.3333, 2191.05) on bodies 13 in component "352303 FRONT - DECOR FRAME DR - FRONT RING TOP"
sketch "TUBE F04 - FRONT RING DT JOINT" plane through (0, 0, 0) normal (0, 1, 0) x (1, 0, 0) in component "352304 FRONT - DECOR FRAME DR - FRONT RING DT JOINT"
  line L0 (261.9888, -2197.7167) -> (261.9888, -2092.243)
  line L1 (261.9888, -2092.243) -> (281.9888, -2099.7022)
  line L2 (281.9888, -2099.7022) -> (281.9888, -2177.7167)
  line L3 (281.9888, -2177.7167) -> (261.9888, -2197.7167)
  point P0 (-5000, 5000)
  dimension "d9017" = 5000
  dimension "d9018" = 5000
  dimension "d9019" = 5261.9888
  dimension "d9020" = 5281.9888
  dimension "d9021" = 7197.7167
  dimension "d9022" = 7092.243
  dimension "d9023" = 7099.7022
  dimension "d9024" = 7177.7167
  constraint vertical L0
  constraint vertical L2
  measures "d9017" horizontal distance of origin P0
  measures "d9018" vertical distance of origin P0
  measures "d9019" horizontal distance of L0.start P0
  measures "d9020" horizontal distance of L1.end P0
  measures "d9021" vertical distance of L0.start P0
  measures "d9022" vertical distance of L0.end P0
  measures "d9023" vertical distance of L1.end P0
  measures "d9024" vertical distance of L2.end P0
extrude "EXTRUDE - TUBE F04" add sketch "TUBE F04 - FRONT RING DT JOINT" along normal blind 20 from surface at -844 separate body makes body 14 in component "352304 FRONT - DECOR FRAME DR - FRONT RING DT JOINT"
shell "SHELL - TUBE F04 (ENDS OPEN)" thickness 1 removed faces 2 at (275.3221, -830.6667, 2184.3833) at (268.6554, -837.3333, 2094.7294) on bodies 14 in component "352304 FRONT - DECOR FRAME DR - FRONT RING DT JOINT"
sketch "TUBE F05 - FRONT RING DIAGONAL" plane through (0, 0, 0) normal (0, 1, 0) x (1, 0, 0) in component "352305 FRONT - DECOR FRAME DR - FRONT RING DIAGONAL"
  line L0 (261.9888, -2092.243) -> (754.6956, -1523.5891)
  line L1 (754.6956, -1523.5891) -> (773.681, -1532.2192)
  line L2 (773.681, -1532.2192) -> (281.9888, -2099.7022)
  line L3 (281.9888, -2099.7022) -> (261.9888, -2092.243)
  point P0 (-5000, 5000)
  dimension "d9029" = 5000
  dimension "d9030" = 5000
  dimension "d9031" = 5261.9888
  dimension "d9032" = 5754.6956
  dimension "d9033" = 5773.681
  dimension "d9034" = 5281.9888
  dimension "d9035" = 7092.243
  dimension "d9036" = 6523.5891
  dimension "d9037" = 6532.2192
  dimension "d9038" = 7099.7022
  measures "d9029" horizontal distance of origin P0
  measures "d9030" vertical distance of origin P0
  measures "d9031" horizontal distance of L0.start P0
  measures "d9032" horizontal distance of L0.end P0
  measures "d9033" horizontal distance of L1.end P0
  measures "d9034" horizontal distance of L2.end P0
  measures "d9035" vertical distance of L0.start P0
  measures "d9036" vertical distance of L0.end P0
  measures "d9037" vertical distance of L1.end P0
  measures "d9038" vertical distance of L2.end P0
extrude "EXTRUDE - TUBE F05" add sketch "TUBE F05 - FRONT RING DIAGONAL" along normal blind 20 from surface at -844 separate body makes body 15 in component "352305 FRONT - DECOR FRAME DR - FRONT RING DIAGONAL"
shell "SHELL - TUBE F05 (ENDS OPEN)" thickness 1 removed faces 2 at (275.3221, -837.3333, 2097.2158) at (761.0241, -837.3333, 1526.4658) on bodies 15 in component "352305 FRONT - DECOR FRAME DR - FRONT RING DIAGONAL"
sketch "TUBE F06 - FRONT RING GLASS EDGE" plane through (0, 0, 0) normal (0, 1, 0) x (1, 0, 0) in component "352306 FRONT - DECOR FRAME DR - FRONT RING GLASS EDGE"
  line L0 (754.6956, -1523.5891) -> (952.9368, -110)
  line L1 (952.9368, -110) -> (970.3277, -130)
  line L2 (970.3277, -130) -> (773.681, -1532.2192)
  line L3 (773.681, -1532.2192) -> (754.6956, -1523.5891)
  point P0 (-5000, 5000)
  dimension "d9043" = 5000
  dimension "d9044" = 5000
  dimension "d9045" = 5754.6956
  dimension "d9047" = 5970.3277
  dimension "d9048" = 5773.681
  dimension "d9049" = 6523.5891
  dimension "d9051" = 5130
  dimension "d9052" = 6532.2192
  measures "d9043" horizontal distance of origin P0
  measures "d9044" vertical distance of origin P0
  measures "d9045" horizontal distance of L0.start P0
  measures "d9047" horizontal distance of L1.end P0
  measures "d9048" horizontal distance of L2.end P0
  measures "d9049" vertical distance of L0.start P0
  measures "d9051" vertical distance of L1.end P0
  measures "d9052" vertical distance of L2.end P0
extrude "EXTRUDE - TUBE F06" add sketch "TUBE F06 - FRONT RING GLASS EDGE" along normal blind 20 from surface at -844 separate body makes body 16 in component "352306 FRONT - DECOR FRAME DR - FRONT RING GLASS EDGE"
shell "SHELL - TUBE F06 (ENDS OPEN)" thickness 1 removed faces 2 at (767.3526, -837.3333, 1529.3425) at (958.7338, -830.6667, 116.6667) on bodies 16 in component "352306 FRONT - DECOR FRAME DR - FRONT RING GLASS EDGE"